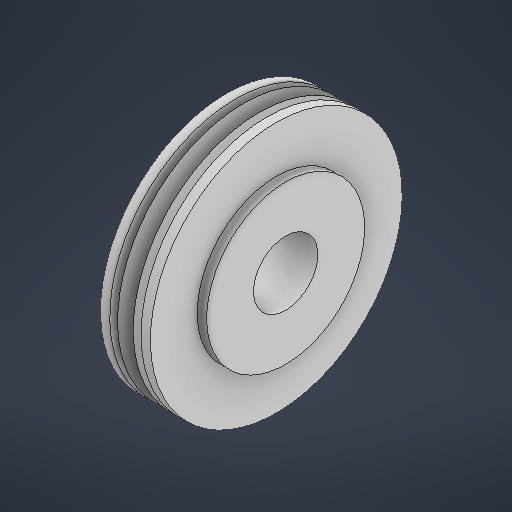
# Autodesk Inventor part: POLEA GRANDE
Saved by Autodesk Inventor 2027.1 (Build 311270010, 270A)
## iProperties
Created: 2026-11-20
Part Number: POLEA GRANDE
Material: Generic
Document SubType Name: Modeling
Designer: ASUS
Density: 1 g/cm^3
Appearance: Default
Author: ASUS
Autodesk Inventor part; units mm, degrees
ref_plane "YZ Plane" through (0, 0, 0) normal (1, 0, 0) x (0, 1, 0)
ref_plane "XZ Plane" through (0, 0, 0) normal (0, 1, 0) x (-1, 0, 0)
ref_plane "XY Plane" through (0, 0, 0) normal (0, 0, 1) x (1, 0, 0)
sketch "Sketch1" plane through (0, 0, 0) normal (0, 0, 1) x (1, 0, 0)
  line L0 (0, 0) -> (0, 10.3)
  line L1 (0, 10.3) -> (0, 40.3)
  line L2 (0, 40.3) -> (-16, 40.3)
  line L3 (-16, 40.3) -> (-13, 40.3)
  line L4 (-13, 40.3) -> (-13, 10.3)
  line L5 (-13, 10.3) -> (-16, 10.3)
  line L6 (-16, 10.3) -> (-16, 40.3)
  line L7 (0, 40.3) -> (-3, 40.3)
  line L8 (-3, 40.3) -> (-3, 10.3)
  line L9 (-3, 10.3) -> (0, 10.3)
  line L10 (-13, 10.3) -> (-3, 10.3)
  line L11 (-13, 40.3) -> (-13, 36.3)
  line L12 (-13, 36.3) -> (-10.5, 40.3)
  line L13 (-8, 36.3) -> (-5.5, 40.3)
  line L14 (-3, 36.6024) -> (-5.5, 40.3)
  line L15 (-10.5, 40.3) -> (-8, 36.3)
  line L16 (0, 10.3) -> (3, 10.3)
  line L17 (3, 10.3) -> (3, 25.3)
  line L18 (3, 25.3) -> (0, 25.3)
  line L19 (0, 0) -> (-16, 0)
  dimension "d0" = 10.3
  dimension "d1" = 30
  dimension "d2" = 16
  dimension "d3" = 3
  dimension "d4" = 3
  dimension "d5" = 4
  dimension "d6" = 2.5
  dimension "d7" = 2.5
  dimension "d8" = 5
  dimension "d9" = 3
  constraints: 40 end point, 8 perpendicular, 6 point on line, 2 horizontal, 2 vertical, 1 midpoint, 1 parallel
  measures "d0" distance of L0.start L0.end
  measures "d1" distance of L0.end L1.end
  measures "d2" distance of L1.end L2.end
  measures "d3" distance of L2.end L3.end
  measures "d4" distance of L1.end L7.end
  measures "d5" distance of L3.end L11.end
  measures "d6" distance of L12.end L3.end
  measures "d7" distance of L7.end L13.end
  measures "d8" distance of L13.start L11.end
  measures "d9" distance of L0.end L16.end
revolve "Revolution1" add sketch "Sketch1" angle 360 about axis through (0, 0, 0) along (-1, 0, 0) contours L9 L8 L2 L1 | L1 L18 L17 L16 | L10 L4 L12 L15 L13 L14 L8 | L5 L6 L2 L4
body "Solid1"
